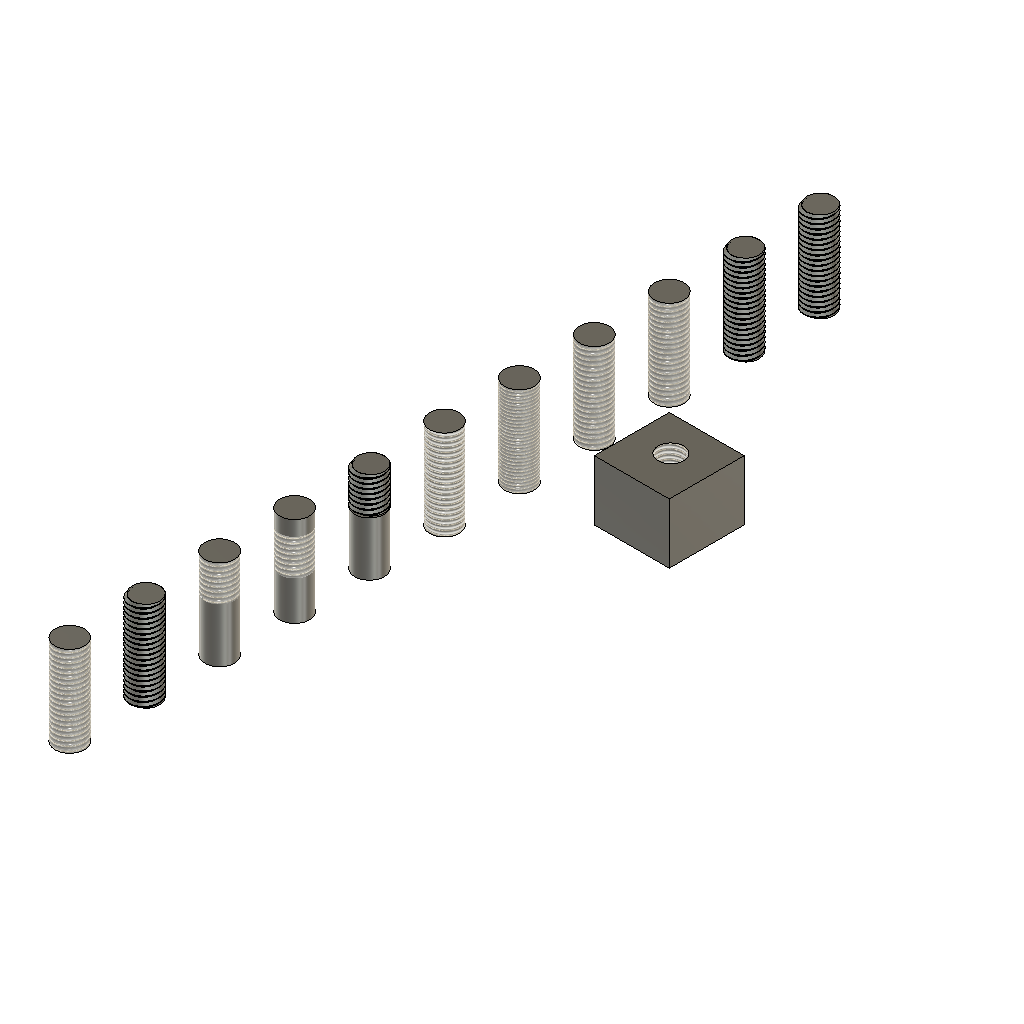
threads (Autodesk Fusion 360 design; units mm, degrees)
part number: 2026-11-13-10-44-39-943
Autodesk Fusion 360 part; units mm, degrees
cylinder "CylinderPrimitive1" add diameter 10 height 30 placed x (1, 0, 0) y (0, 1, 0) z (0, 0, 1) at (0, 0, 0) makes body 1
cylinder "CylinderPrimitive2" add diameter 10 height 30 placed x (1, 0, 0) y (0, 1, 0) z (0, 0, 1) at (0, 25, 0) separate body makes body 2
cylinder "CylinderPrimitive3" add diameter 10 height 30 placed x (1, 0, 0) y (0, 1, 0) z (0, 0, 1) at (0, 50, 0) separate body makes body 3
cylinder "CylinderPrimitive4" add diameter 10 height 30 placed x (1, 0, 0) y (0, 1, 0) z (0, 0, 1) at (0, 75, 0) separate body makes body 4
cylinder "CylinderPrimitive5" add diameter 10 height 30 placed x (1, 0, 0) y (0, 1, 0) z (0, 0, 1) at (0, -25, 0) separate body makes body 5
cylinder "CylinderPrimitive6" add diameter 10 height 30 placed x (1, 0, 0) y (0, 1, 0) z (0, 0, 1) at (0, -50, 0) separate body makes body 6
cylinder "CylinderPrimitive7" add diameter 10 height 30 placed x (1, 0, 0) y (0, 1, 0) z (0, 0, 1) at (0, -75, 0) separate body makes body 7
cylinder "CylinderPrimitive8" add diameter 10 height 30 placed x (1, 0, 0) y (0, 1, 0) z (0, 0, 1) at (0, -100, 0) separate body makes body 8
cylinder "CylinderPrimitive9" add diameter 10 height 30 placed x (1, 0, 0) y (0, 1, 0) z (0, 0, 1) at (0, -125, 0) separate body makes body 9
cylinder "CylinderPrimitive10" add diameter 10 height 30 placed x (1, 0, 0) y (0, 1, 0) z (0, 0, 1) at (0, -150, 0) separate body makes body 10
cylinder "CylinderPrimitive11" add diameter 10 height 30 placed x (1, 0, 0) y (0, 1, 0) z (0, 0, 1) at (0, 100, 0) separate body makes body 11
thread "cos_full" "ISO Metric profile 10.0 M10x1.5 M10x1.5 6g" major diameter 9.85 minor diameter 8.141 pitch 1.5 angle 60 resizes the face on face at (-4.6074, -151.9422, 10) on bodies 10
thread "mod_full" "ISO Metric profile 10.0 M10x1.5 M10x1.5 6g" major diameter 9.85 minor diameter 8.141 pitch 1.5 angle 60 modelled right hand crest width 0.2177 on face at (4.9752, -125.4978, 10) crest through (4.925, -125, -0.375) on bodies 9
thread "cos_len12" "ISO Metric profile 10.0 M10x1.5 M10x1.5 6g" major diameter 9.85 minor diameter 8.141 pitch 1.5 angle 60 resizes the face on face at (4.9752, -100.4978, 10) from (0, -100, 18) to (0, -100, 30) on bodies 8
thread "cos_len12_off5" "ISO Metric profile 10.0 M10x1.5 M10x1.5 6g" major diameter 9.85 minor diameter 8.141 pitch 1.5 angle 60 resizes the face on face at (4.9752, -75.4978, 10) from (0, -75, 13) to (0, -75, 25) on bodies 7
thread "mod_len12" "ISO Metric profile 10.0 M10x1.5 M10x1.5 6g" major diameter 9.85 minor diameter 8.141 pitch 1.5 angle 60 modelled right hand crest width 0.2177 on face at (4.9752, -50.4978, 10) from (0, -50, 18) to (0, -50, 30) crest through (4.925, -50, -0.375) on bodies 6
thread "cos_left" "ISO Metric profile 10.0 M10x1.5 M10x1.5 6g" major diameter 9.85 minor diameter 8.141 pitch 1.5 angle 60 resizes the face on face at (4.9752, -25.4978, 10) on bodies 5
thread "cos_fine" "ISO Metric profile 10.0 M10x1 M10x1 6g" major diameter 9.884 minor diameter 8.744 pitch 1 angle 60 resizes the face on face at (4.9752, -0.4978, 10) on bodies 1
thread "cos_2faces" "ISO Metric profile 10.0 M10x1.5 M10x1.5 6g" major diameter 9.85 minor diameter 8.141 pitch 1.5 angle 60 resizes the face on face at (4.9752, 49.5022, 10) on face at (4.9752, 24.5022, 10) on bodies 2 3
thread "mod_2faces" "ISO Metric profile 10.0 M10x1.5 M10x1.5 6g" major diameter 9.85 minor diameter 8.141 pitch 1.5 angle 60 modelled right hand crest width 0.2177 on face at (4.9752, 99.5022, 10) crest through (4.925, 100, -0.375) on face at (4.9752, 74.5022, 10) crest through (4.925, 75, -0.375) on bodies 4 11
box "BoxPrimitive1" add length 25 width 25 height 20 placed x (0, 1, 0) y (-1, 0, 0) z (0, 0, 1) at (50, 0, 0) separate body makes body 12
hole "Hole1" at (37.0976, 13.4529, 20) direction (0, 0, -1) diameter 8.5 depth 20 tip angle 118 bodies 12
thread "int_cos_full" "ISO Metric profile 10.0 M10x1.5 M10x1.5 6H" major diameter 10.198 minor diameter 8.526 pitch 1.5 angle 60 resizes the face on face at (37.3094, 9.2082, 13.3333) on bodies 12
